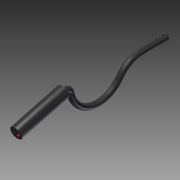
# Autodesk Inventor part: cyclic
Saved by Autodesk Inventor 2015 (Build 190159000, 159)
## iProperties
Created: 2022-11-07
Part Number: cyclic
Material: Generic
Document SubType Name: Modeling
Designer: Pavel Brodský
Density: 1 g/cm^3
Appearance: Default
Author: Pavel Brodský
Autodesk Inventor part; units mm, degrees
ref_plane "YZ Plane" through (0, 0, 0) normal (1, 0, 0) x (0, 1, 0)
ref_plane "XZ Plane" through (0, 0, 0) normal (0, 1, 0) x (-1, 0, 0)
ref_plane "XY Plane" through (0, 0, 0) normal (0, 0, 1) x (1, 0, 0)
sketch "Náčrt1" plane through (0, 0, 0) normal (0, 1, 0) x (-1, 0, 0)
  circle A0 centre (0, 0) radius 9.5
  circle A1 centre (0, 0) radius 8.5
  dimension "d0" = 19
  dimension "d1" = 1
  constraints: 2 centre point, 1 coincident
  measures "d0" diameter of A0
  measures "d1" radial gap between concentric circles of A0 A1
sketch "Náčrt2" plane through (0, 0, 0) normal (1, 0, 0) x (0, 1, 0)
  line L0 (0, 0) -> (-85, 0)
  arc A0 (-85, 0) -> (-162.4597, -40) centre (-85, -95) ccw
  arc A1 (-333.5693, -0.9588) -> (-162.4597, -40) centre (-239.9193, 15) ccw
  arc A2 (-333.5693, -0.9588) -> (-358.4615, 15) centre (-353.2851, -4.3185) ccw
  line L1 (-358.4615, 15) -> (-528.4615, -30.5514) construction
  line L2 (-358.4615, 15) -> (-485.6083, 15) construction
  dimension "d2" = 95
  dimension "d3" = 95
  dimension "d4" = 20
  dimension "d5" = 85
  dimension "d6" = 15
  dimension "d7" = 170
  dimension "d8" = 15
  constraints: 6 end point, 6 point on circle, 4 tangent, 3 centre point, 2 horizontal, 1 horizontal alignment
  measures "d2" radius of A1
  measures "d3" radius of A0
  measures "d4" radius of A2
  measures "d5" distance of L0.start L0.end
  measures "d6" vertical distance of A1.centre L0.start
  measures "d7" horizontal distance of L1.start L1.end
  measures "d8" angle of L2 L1
sweep "Tažení1" add profiles "Náčrt1" path "Náčrt2"
sketch "Náčrt3" plane through (0, 0, 0) normal (0, 0, 1) x (1, 0, 0)
  circle A0 centre (0, -10) radius 2.5
  circle A1 centre (0, -35) radius 2.5
  line L0 (-9.5, 0) -> (9.5, 0) projected
  point P0 (0, 0)
  dimension "d11" = 5
  dimension "d12" = 5
  dimension "d13" = 10
  dimension "d14" = 25
  constraints: 2 centre point
  measures "d11" diameter of A0
  measures "d12" diameter of A1
  measures "d13" distance from line of L0 A0.centre
  measures "d14" distance of A0.centre A1.centre
extrude "Vysunutí1" cut sketch "Náčrt3" along normal through all both and the other way through all
sketch "Náčrt4" plane through (0, -358.4615, 15) normal (0, -0.9659258, -0.258819) x (1, 0, 0)
  circle A0 centre (0, 0) radius 20
  point P0 (0, -107.2655)
  dimension "d17" = 40
  constraints: 1 centre point
  measures "d17" diameter of A0
extrude "Vysunutí2" add sketch "Náčrt4" along normal blind 170
sketch "Náčrt5" plane through (0, -522.6689, -28.9992) normal (0, -0.9659258, -0.258819) x (1, 0, 0)
  circle A0 centre (11.0485, 0) radius 3.4455
  point P0 (0, -107.2655)
  constraints: 1 centre point
extrude "Vysunutí3" add sketch "Náčrt5" along normal blind 8
equation "\"d12\" = d11"
